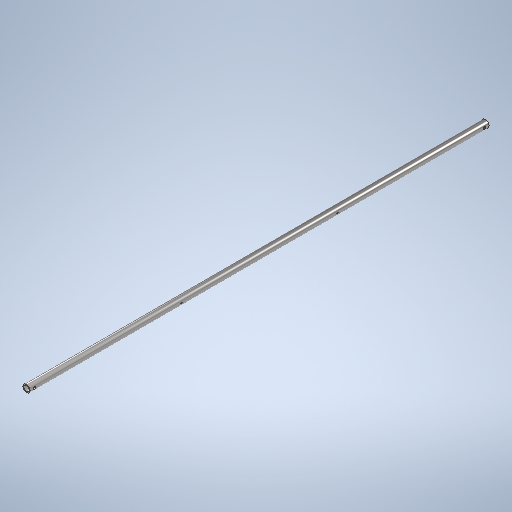
# Autodesk Inventor part: Steel Rod
Saved by Autodesk Inventor 2026.2 (Build 302298000, 298)
## iProperties
Created: 2026-07-17
Part Number: Steel Rod
Material: Stainless Steel
Document SubType Name: Modeling
Designer: Taiye Raji
Density: 8 g/cm^3
Appearance: Semi-Polished
Mass: 1651.78 g
Surface Area: 525.855 cm^2
Volume: 206.472 cm^3
Author: Taiye Raji
Autodesk Inventor part; units mm, degrees
ref_plane "YZ Plane" through (0, 0, 0) normal (1, 0, 0) x (0, 1, 0)
ref_plane "XZ Plane" through (0, 0, 0) normal (0, 1, 0) x (-1, 0, 0)
ref_plane "XY Plane" through (0, 0, 0) normal (0, 0, 1) x (1, 0, 0)
sketch "Sketch1" plane through (0, 0, 0) normal (0, 0, 1) x (1, 0, 0)
  circle A0 centre (0, 0) radius 8
  circle A1 centre (0, 0) radius 6
  dimension "d0" = 16
  dimension "d11" = 12
  constraints: 2 centre point, 2 coincident
  measures "d0" diameter of A0
  measures "d11" diameter of A1
extrude "Extrusion1" add sketch "Sketch1" against normal blind 1030
sketch "Sketch2" plane through (0, 0, 0) normal (1, 0, 0) x (0, 1, 0)
  circle A0 centre (0, -10) radius 3
  line L0 (8, 0) -> (-8, 0) projected
  circle A1 centre (0, -1020) radius 3
  line L1 (-8, -1030) -> (8, -1030) projected
  line L2 (8, 0) -> (8, -1030) projected
  line L3 (8, -515) -> (-50.8, -515) construction
  circle A2 centre (0, -690) radius 1.5
  circle A3 centre (0, -340) radius 1.5
  point P0 (0, 0)
  point P1 (0, 0)
  point P2 (0, -1030)
  point P3 (-21.4, -515)
  dimension "d3" = 6
  dimension "d4" = 10
  dimension "d5" = 6
  dimension "d6" = 10
  dimension "d12" = 3
  dimension "d13" = 58.8
  dimension "d14" = 515
  dimension "d15" = 3
  dimension "d16" = 175
  constraints: 4 centre point, 4 midpoint, 3 vertical alignment, 2 end point, 1 horizontal, 1 symmetric about line, 1 other
  measures "d3" diameter of A0
  measures "d4" distance from line of A0.centre L0
  measures "d5" diameter of A1
  measures "d6" distance from line of L1 A1.centre
  measures "d12" diameter of A2
  measures "d13" distance of L3.start L3.end
  measures "d14" distance from line of point (-21.4, -515) L0
  measures "d15" diameter of A3
  measures "d16" distance from line of A2.centre L3
extrude "Extrusion2" cut sketch "Sketch2" along normal blind 20 and the other way blind 20
body "Solid1"
